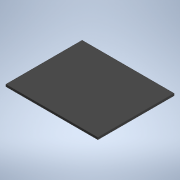
# Autodesk Inventor part: ultima verticala la tevi
Saved by Autodesk Inventor 2022.6 (Build 266554000, 554)
## iProperties
Created: 2026-10-28
Part Number: ultima verticala la tevi
Material: Generic
Document SubType Name: Modeling
Designer: Dragos Macovei
Density: 1 g/cm^3
Appearance: Default
Author: Dragos Macovei
Autodesk Inventor part; units mm, degrees
ref_plane "YZ Plane" through (0, 0, 0) normal (1, 0, 0) x (0, 1, 0)
ref_plane "XZ Plane" through (0, 0, 0) normal (0, 1, 0) x (-1, 0, 0)
ref_plane "XY Plane" through (0, 0, 0) normal (0, 0, 1) x (1, 0, 0)
sketch "Sketch1" plane through (0, 0, 0) normal (0, 1, 0) x (-1, 0, 0)
  line L0 (-67.3101, -145.3962) -> (702.6899, -145.3962)
  line L1 (702.6899, -145.3962) -> (702.6899, 492.6038)
  line L2 (702.6899, 492.6038) -> (-67.3101, 492.6038)
  line L3 (-67.3101, 492.6038) -> (-67.3101, -145.3962)
  point P0 (0, 0)
  dimension "d0" = 770
  dimension "d1" = 638
  constraints: 8 end point, 2 parallel, 1 horizontal, 1 perpendicular
  measures "d0" distance of L2.end L1.end
  measures "d1" distance of L1.end L0.end
extrude "Extrusion1" add sketch "Sketch1" along normal blind 18
body "Solid1"
